Autodesk Inventor part; units mm, degrees
(part 2 of 2)
sketch "Sketch6" plane through (-20, -44, -10) normal (0, -1, 0) x (1, 0, 0)
  arc A0 (32, 4.5) -> (34, 6.5) centre (32, 6.5) ccw projected
  line L0 (34, 13.5) -> (34, 6.5) projected
  arc A1 (34, 13.5) -> (32, 15.5) centre (32, 13.5) ccw projected
  line L1 (8, 15.5) -> (32, 15.5) projected
  arc A2 (8, 15.5) -> (6, 13.5) centre (8, 13.5) ccw projected
  line L2 (6, 6.5) -> (6, 13.5) projected
  arc A3 (6, 6.5) -> (8, 4.5) centre (8, 6.5) ccw projected
  line L3 (32, 4.5) -> (8, 4.5) projected
  line L4 (34, 10) -> (6, 10)
  line L5 (31.2608, 8.1622) -> (8.7392, 8.1622) construction
  line L6 (8.7392, 8.1622) -> (8.7392, 11.8378) construction
  line L7 (8.7392, 11.8378) -> (31.2608, 11.8378) construction
  line L8 (31.2608, 11.8378) -> (31.2608, 8.1622) construction
  line L9 (6, 6.5) -> (6, 13.5) projected
  line L10 (30.8827, 11.2102) -> (30.8856, 8.1622)
  line L11 (30.8856, 8.1622) -> (29.0184, 8.168)
  line L12 (29.0184, 8.168) -> (29.0184, 8.674)
  line L13 (29.0184, 8.674) -> (30.2778, 8.6682)
  line L14 (30.2778, 8.6682) -> (30.2778, 9.375)
  line L15 (30.2778, 9.375) -> (29.2133, 9.375)
  line L16 (29.2133, 9.375) -> (29.2133, 9.8868)
  line L17 (29.2133, 9.8868) -> (30.2778, 9.8868)
  line L18 (30.2778, 9.8868) -> (30.2778, 10.7012)
  line L19 (30.2778, 10.7012) -> (28.9748, 10.7012)
  line L20 (28.9748, 10.7012) -> (28.9748, 11.2102)
  line L21 (28.9748, 11.2102) -> (30.8827, 11.2102)
  line L22 (28.4047, 11.2102) -> (28.4047, 8.9067)
  line L23 (28.4047, 8.9067) -> (27.9132, 8.9067)
  line L24 (27.9132, 8.9067) -> (27.8667, 9.215)
  line L25 (27.8667, 9.215) -> (27.8551, 9.215)
  spline S0 degree 2 poles (27.8551, 9.215) (27.7096, 9.0667) (27.3723, 8.8485) (27.1483, 8.8485) knots 0 0 0 1 2 2 2
  spline S1 degree 2 poles (27.1483, 8.8485) (26.9011, 8.8485) (26.6015, 9.058) (26.5172, 9.2528) knots 0 0 0 1 2 2 2
  spline S2 degree 2 poles (26.5172, 9.2528) (26.3543, 9.0841) (26.0053, 8.8485) (25.7814, 8.8485) knots 0 0 0 1 2 2 2
  spline S3 degree 2 poles (25.7814, 8.8485) (25.412, 8.8485) (25.0717, 9.3401) (25.0717, 9.7763) knots 0 0 0 1 2 2 2
  line L26 (25.0717, 9.7763) -> (25.0717, 11.2102)
  line L27 (25.0717, 11.2102) -> (25.6709, 11.2102)
  line L28 (25.6709, 11.2102) -> (25.6709, 9.849)
  spline S4 degree 2 poles (25.6709, 9.849) (25.6709, 9.5815) (25.8279, 9.3691) (25.9908, 9.3691) knots 0 0 0 1 2 2 2
  spline S5 degree 2 poles (25.9908, 9.3691) (26.0897, 9.3691) (26.3078, 9.4942) (26.4358, 9.628) knots 0 0 0 1 2 2 2
  line L29 (26.4358, 9.628) -> (26.4358, 11.2102)
  line L30 (26.4358, 11.2102) -> (27.0407, 11.2102)
  line L31 (27.0407, 11.2102) -> (27.0407, 9.849)
  spline S6 degree 2 poles (27.0407, 9.849) (27.0407, 9.5815) (27.1978, 9.3691) (27.3606, 9.3691) knots 0 0 0 1 2 2 2
  spline S7 degree 2 poles (27.3606, 9.3691) (27.4566, 9.3691) (27.6806, 9.4942) (27.7998, 9.628) knots 0 0 0 1 2 2 2
  line L32 (27.7998, 9.628) -> (27.7998, 11.2102)
  line L33 (27.7998, 11.2102) -> (28.4047, 11.2102)
  spline S8 degree 2 poles (23.4372, 11.2683) (23.76, 11.2683) (24.2777, 10.9804) (24.586, 10.4365) (24.586, 10.0584) knots 0 0 0 1 2 3 3 3
  spline S9 degree 2 poles (24.586, 10.0584) (24.586, 9.7792) (24.4086, 9.3342) (24.1003, 9.0172) (23.7164, 8.8485) (23.5128, 8.8485) knots 0 0 0 1 2 3 4 4 4
  spline S10 degree 2 poles (23.5128, 8.8485) (23.1958, 8.8485) (22.7683, 9.1336) (22.5501, 9.6309) (22.5501, 9.9508) knots 0 0 0 1 2 3 3 3
  spline S11 degree 2 poles (22.5501, 9.9508) (22.5501, 10.0352) (22.5676, 10.1864) (22.5792, 10.23) knots 0 0 0 1 2 2 2
  line L34 (22.5792, 10.23) -> (23.9985, 10.23)
  spline S12 degree 2 poles (23.9985, 10.23) (23.9723, 10.4162) (23.8008, 10.6721) (23.5274, 10.8001) (23.3558, 10.8001) knots 0 0 0 1 2 3 3 3
  spline S13 degree 2 poles (23.3558, 10.8001) (23.2162, 10.8001) (22.969, 10.7216) (22.841, 10.643) knots 0 0 0 1 2 2 2
  line L35 (22.841, 10.643) -> (22.6374, 11.0124)
  spline S14 degree 2 poles (22.6374, 11.0124) (22.8061, 11.1287) (23.2249, 11.2683) (23.4372, 11.2683) knots 0 0 0 1 2 2 2
  line L36 (24.0102, 9.8229) -> (23.0678, 9.8229)
  spline S15 degree 2 poles (23.0678, 9.8229) (23.0678, 9.5931) (23.2772, 9.3197) (23.5041, 9.3197) knots 0 0 0 1 2 2 2
  spline S16 degree 2 poles (23.5041, 9.3197) (23.6233, 9.3197) (23.8357, 9.4302) (23.984, 9.6571) (24.0102, 9.8229) knots 0 0 0 1 2 3 3 3
  line L37 (22.0499, 11.2102) -> (22.0499, 8.9067)
  line L38 (22.0499, 8.9067) -> (21.5584, 8.9067)
  line L39 (21.5584, 8.9067) -> (21.5118, 9.3139)
  line L40 (21.5118, 9.3139) -> (21.5002, 9.3139)
  spline S17 degree 2 poles (21.5002, 9.3139) (21.3722, 9.087) (21.0261, 8.8485) (20.8458, 8.8485) knots 0 0 0 1 2 2 2
  spline S18 degree 2 poles (20.8458, 8.8485) (20.7469, 8.8485) (20.6277, 8.8776) (20.5782, 8.898) knots 0 0 0 1 2 2 2
  line L41 (20.5782, 8.898) -> (20.6771, 9.4215)
  spline S19 degree 2 poles (20.6771, 9.4215) (20.744, 9.404) (20.8458, 9.3837) (20.9243, 9.3837) knots 0 0 0 1 2 2 2
  spline S20 degree 2 poles (20.9243, 9.3837) (21.0552, 9.3837) (21.3461, 9.5902) (21.445, 9.8374) knots 0 0 0 1 2 2 2
  line L42 (21.445, 9.8374) -> (21.445, 11.2102)
  line L43 (21.445, 11.2102) -> (22.0499, 11.2102)
  spline S21 degree 2 poles (19.444, 12.2107) (19.7145, 12.2107) (20.1507, 12.0827) (20.4008, 11.8238) (20.4008, 11.6173) knots 0 0 0 1 2 3 3 3
  spline S22 degree 2 poles (20.4008, 11.6173) (20.4008, 11.4719) (20.238, 11.2276) (20.0722, 11.1404) knots 0 0 0 1 2 2 2
  line L44 (20.0722, 11.1404) -> (20.0722, 11.12)
  spline S23 degree 2 poles (20.0722, 11.12) (20.1623, 11.0618) (20.2816, 10.8728) (20.2816, 10.7303) knots 0 0 0 1 2 2 2
  spline S24 degree 2 poles (20.2816, 10.7303) (20.2816, 10.6023) (20.1304, 10.3755) (20.0286, 10.2998) knots 0 0 0 1 2 2 2
  line L45 (20.0286, 10.2998) -> (20.0286, 10.2853)
  spline S25 degree 2 poles (20.0286, 10.2853) (20.1478, 10.198) (20.3369, 9.8868) (20.3369, 9.6803) knots 0 0 0 1 2 2 2
  spline S26 degree 2 poles (20.3369, 9.6803) (20.3369, 9.4099) (20.0751, 9.0376) (19.6476, 8.8485) (19.4091, 8.8485) knots 0 0 0 1 2 3 3 3
  spline S27 degree 2 poles (19.4091, 8.8485) (19.3073, 8.8485) (19.1299, 8.8834) (19.0572, 8.9067) knots 0 0 0 1 2 2 2
  line L46 (19.0572, 8.9067) -> (18.2312, 8.9067)
  line L47 (18.2312, 8.9067) -> (18.2312, 9.3517)
  line L48 (18.2312, 9.3517) -> (18.6209, 9.3517)
  spline S28 degree 2 poles (18.6209, 9.3517) (18.5744, 9.4128) (18.5191, 9.5931) (18.5191, 9.7007) knots 0 0 0 1 2 2 2
  spline S29 degree 2 poles (18.5191, 9.7007) (18.5191, 9.9596) (18.7576, 10.3086) (19.1589, 10.4831) (19.4091, 10.4831) knots 0 0 0 1 2 3 3 3
  spline S30 degree 2 poles (19.4091, 10.4831) (19.4731, 10.4831) (19.6272, 10.454) (19.7057, 10.4278) knots 0 0 0 1 2 2 2
  spline S31 degree 2 poles (19.7057, 10.4278) (19.7523, 10.4685) (19.8046, 10.5558) (19.8046, 10.6314) knots 0 0 0 1 2 2 2
  spline S32 degree 2 poles (19.8046, 10.6314) (19.8046, 10.7157) (19.6447, 10.8146) (19.444, 10.8146) knots 0 0 0 1 2 2 2
  line L49 (19.444, 10.8146) -> (19.0484, 10.8146)
  spline S33 degree 2 poles (19.0484, 10.8146) (18.6325, 10.8146) (18.1875, 11.0909) (18.1875, 11.3905) knots 0 0 0 1 2 2 2
  spline S34 degree 2 poles (18.1875, 11.3905) (18.1875, 11.6261) (18.4987, 11.9925) (19.0601, 12.2107) (19.444, 12.2107) knots 0 0 0 1 2 3 3 3
  spline S35 degree 2 poles (19.3538, 11.8238) (19.1764, 11.8238) (18.9176, 11.7337) (18.7692, 11.5853) (18.7692, 11.4952) knots 0 0 0 1 2 3 3 3
  spline S36 degree 2 poles (18.7692, 11.4952) (18.7692, 11.3701) (18.967, 11.2829) (19.1502, 11.2829) knots 0 0 0 1 2 2 2
  line L50 (19.1502, 11.2829) -> (19.4352, 11.2829)
  spline S37 degree 2 poles (19.4352, 11.2829) (19.537, 11.2829) (19.6854, 11.2712) (19.7523, 11.2567) knots 0 0 0 1 2 2 2
  spline S38 degree 2 poles (19.7523, 11.2567) (19.8308, 11.3178) (19.9006, 11.4516) (19.9006, 11.5272) knots 0 0 0 1 2 2 2
  spline S39 degree 2 poles (19.9006, 11.5272) (19.9006, 11.6668) (19.6039, 11.8238) (19.3538, 11.8238) knots 0 0 0 1 2 2 2
  spline S40 degree 2 poles (19.4091, 10.1079) (19.3073, 10.1079) (19.1444, 10.009) (19.0455, 9.817) (19.0455, 9.6803) knots 0 0 0 1 2 3 3 3
  spline S41 degree 2 poles (19.0455, 9.6803) (19.0455, 9.5437) (19.1444, 9.3604) (19.3073, 9.2644) (19.4091, 9.2644) knots 0 0 0 1 2 3 3 3
  spline S42 degree 2 poles (19.4091, 9.2644) (19.508, 9.2644) (19.6737, 9.3604) (19.7668, 9.5437) (19.7668, 9.6803) knots 0 0 0 1 2 3 3 3
  spline S43 degree 2 poles (19.7668, 9.6803) (19.7668, 9.817) (19.6737, 10.009) (19.508, 10.1079) (19.4091, 10.1079) knots 0 0 0 1 2 3 3 3
  spline S44 degree 2 poles (16.7944, 11.2683) (17.1173, 11.2683) (17.6349, 10.9804) (17.9432, 10.4365) (17.9432, 10.0584) knots 0 0 0 1 2 3 3 3
  spline S45 degree 2 poles (17.9432, 10.0584) (17.9432, 9.7792) (17.7658, 9.3342) (17.4575, 9.0172) (17.0736, 8.8485) (16.87, 8.8485) knots 0 0 0 1 2 3 4 4 4
  spline S46 degree 2 poles (16.87, 8.8485) (16.553, 8.8485) (16.1255, 9.1336) (15.9074, 9.6309) (15.9074, 9.9508) knots 0 0 0 1 2 3 3 3
  spline S47 degree 2 poles (15.9074, 9.9508) (15.9074, 10.0352) (15.9248, 10.1864) (15.9364, 10.23) knots 0 0 0 1 2 2 2
  line L51 (15.9364, 10.23) -> (17.3557, 10.23)
  spline S48 degree 2 poles (17.3557, 10.23) (17.3296, 10.4162) (17.158, 10.6721) (16.8846, 10.8001) (16.713, 10.8001) knots 0 0 0 1 2 3 3 3
  spline S49 degree 2 poles (16.713, 10.8001) (16.5734, 10.8001) (16.3262, 10.7216) (16.1982, 10.643) knots 0 0 0 1 2 2 2
  line L52 (16.1982, 10.643) -> (15.9946, 11.0124)
  spline S50 degree 2 poles (15.9946, 11.0124) (16.1633, 11.1287) (16.5821, 11.2683) (16.7944, 11.2683) knots 0 0 0 1 2 2 2
  line L53 (17.3674, 9.8229) -> (16.4251, 9.8229)
  spline S51 degree 2 poles (16.4251, 9.8229) (16.4251, 9.5931) (16.6345, 9.3197) (16.8613, 9.3197) knots 0 0 0 1 2 2 2
  spline S52 degree 2 poles (16.8613, 9.3197) (16.9806, 9.3197) (17.1929, 9.4302) (17.3412, 9.6571) (17.3674, 9.8229) knots 0 0 0 1 2 3 3 3
  line L54 (15.4071, 11.2102) -> (15.4071, 8.9067)
  line L55 (15.4071, 8.9067) -> (14.9156, 8.9067)
  line L56 (14.9156, 8.9067) -> (14.8691, 9.2121)
  line L57 (14.8691, 9.2121) -> (14.8574, 9.2121)
  spline S53 degree 2 poles (14.8574, 9.2121) (14.7033, 9.0638) (14.3426, 8.8485) (14.1071, 8.8485) knots 0 0 0 1 2 2 2
  spline S54 degree 2 poles (14.1071, 8.8485) (13.7348, 8.8485) (13.3974, 9.3401) (13.3974, 9.7763) knots 0 0 0 1 2 2 2
  line L58 (13.3974, 9.7763) -> (13.3974, 11.2102)
  line L59 (13.3974, 11.2102) -> (14.0024, 11.2102)
  line L60 (14.0024, 11.2102) -> (14.0024, 9.849)
  spline S55 degree 2 poles (14.0024, 9.849) (14.0024, 9.5815) (14.1536, 9.3691) (14.3252, 9.3691) knots 0 0 0 1 2 2 2
  spline S56 degree 2 poles (14.3252, 9.3691) (14.4648, 9.3691) (14.6771, 9.5) (14.8022, 9.628) knots 0 0 0 1 2 2 2
  line L61 (14.8022, 9.628) -> (14.8022, 11.2102)
  line L62 (14.8022, 11.2102) -> (15.4071, 11.2102)
  spline S57 degree 2 poles (11.792, 11.2683) (12.109, 11.2683) (12.618, 10.9804) (12.9146, 10.4423) (12.9146, 10.0584) knots 0 0 0 1 2 3 3 3
  spline S58 degree 2 poles (12.9146, 10.0584) (12.9146, 9.6774) (12.5889, 9.1365) (12.0508, 8.8485) (11.7367, 8.8485) knots 0 0 0 1 2 3 3 3
  spline S59 degree 2 poles (11.7367, 8.8485) (11.5244, 8.8485) (11.1958, 8.994) (11.0678, 9.1074) knots 0 0 0 1 2 2 2
  line L63 (11.0678, 9.1074) -> (11.3557, 9.4913)
  spline S60 degree 2 poles (11.3557, 9.4913) (11.4372, 9.4157) (11.6117, 9.343) (11.7047, 9.343) knots 0 0 0 1 2 2 2
  spline S61 degree 2 poles (11.7047, 9.343) (11.8821, 9.343) (12.1497, 9.5204) (12.2922, 9.8403) (12.2922, 10.0584) knots 0 0 0 1 2 3 3 3
  spline S62 degree 2 poles (12.2922, 10.0584) (12.2922, 10.2766) (12.1497, 10.5965) (11.8909, 10.7739) (11.7251, 10.7739) knots 0 0 0 1 2 3 3 3
  spline S63 degree 2 poles (11.7251, 10.7739) (11.6029, 10.7739) (11.3732, 10.6663) (11.2772, 10.5878) knots 0 0 0 1 2 2 2
  line L64 (11.2772, 10.5878) -> (11.0387, 10.9891)
  spline S64 degree 2 poles (11.0387, 10.9891) (11.2045, 11.1316) (11.6029, 11.2683) (11.792, 11.2683) knots 0 0 0 1 2 2 2
  spline S65 degree 2 poles (10.4018, 12.1321) (10.5036, 12.1321) (10.6519, 12.106) (10.7188, 12.0856) knots 0 0 0 1 2 2 2
  line L65 (10.7188, 12.0856) -> (10.6083, 11.6261)
  spline S66 degree 2 poles (10.6083, 11.6261) (10.5734, 11.6348) (10.489, 11.6551) (10.4483, 11.6551) knots 0 0 0 1 2 2 2
  spline S67 degree 2 poles (10.4483, 11.6551) (10.2709, 11.6551) (10.0644, 11.4574) (10.0149, 11.3061) knots 0 0 0 1 2 2 2
  line L66 (10.0149, 11.3061) -> (9.9742, 11.1636)
  line L67 (9.9742, 11.1636) -> (10.87, 8.9067)
  line L68 (10.87, 8.9067) -> (10.2622, 8.9067)
  line L69 (10.2622, 8.9067) -> (9.8957, 9.977)
  spline S68 degree 2 poles (9.8957, 9.977) (9.8434, 10.1341) (9.7532, 10.4627) (9.7038, 10.6256) knots 0 0 0 1 2 2 2
  line L70 (9.7038, 10.6256) -> (9.6834, 10.6256)
  spline S69 degree 2 poles (9.6834, 10.6256) (9.6456, 10.4627) (9.5583, 10.137) (9.5176, 9.977) knots 0 0 0 1 2 2 2
  line L71 (9.5176, 9.977) -> (9.2006, 8.9067)
  line L72 (9.2006, 8.9067) -> (8.6218, 8.9067)
  line L73 (8.6218, 8.9067) -> (9.4391, 11.28)
  spline S70 degree 2 poles (9.4391, 11.28) (9.538, 11.5504) (9.7939, 11.9344) (10.1429, 12.1321) (10.4018, 12.1321) knots 0 0 0 1 2 3 3 3
  point P0 (20, 10)
  point P1 (20, 8.1622)
  point P2 (20, 4.5)
  point P3 (8.7392, 10)
  constraints: 6 midpoint, 2 end point, 1 horizontal alignment, 1 vertical alignment, 2 other
emboss "Emboss1" sketch "Sketch6" operation add depth 0.5 direction (0, 1, 0) contours L10 L11 L12 L13 L14 L15 L16 L17 L18 L4 | L4 L18 L19 L20 L21 L10 | L73 S70 S65 L65 S66 S67 L66 L67 L4 S68 L70 S69 | L4 S69 L71 L72 L73 | L22 L23 L24 L25 S0 S1 S2 S3 L26 L4 L28 S4 S5 L29 L31 S6 S7 L32 | L4 L32 L33 L22 | L4 L67 L68 L69 S68 | L4 L29 L30 L31 | S61 S62 S63 L64 S64 S57 S58 L4 | L4 S58 S59 L63 S60 S61 | L4 L26 L27 L28 | L58 L59 L60 L4 | L4 L60 S55 S56 L61 L54 L55 L56 L57 S53 S54 L58 | S9 S10 S11 L4 | L4 S11 L34 S12 S13 L35 S14 S8 S9 | L61 L62 L54 L4 | L37 L38 L39 L40 S17 S18 L41 S19 S20 L42 L4 | L4 L42 L43 L37 | S47 L51 S48 S49 L52 S50 S44 S45 L4 | L4 S45 S46 S47 | S25 S26 S27 L46 L47 L48 S28 S29 L4 S40 S41 S42 S43 | L4 S43 S40 S29 S30 S31 S32 L49 S33 S34 S21 S22 L44 S23 S24 L45 S25
sketch "Sketch7" plane through (-22.5, 27.5, -10) normal (0, 0, -1) x (-1, 0, 0)
  line L0 (-42.5, -67.5) -> (-2.5, -67.5) projected
  arc A0 (-2.5, -67.5) -> (7.5, -57.5) centre (-2.5, -57.5) ccw projected
  line L1 (7.5, -57.5) -> (7.5, 2.5) projected
  arc A1 (7.5, 2.5) -> (-2.5, 12.5) centre (-2.5, 2.5) ccw projected
  line L2 (-2.5, 12.5) -> (-42.5, 12.5) projected
  arc A2 (-42.5, 12.5) -> (-52.5, 2.5) centre (-42.5, 2.5) ccw projected
  line L3 (-52.5, 2.5) -> (-52.5, -57.5) projected
  arc A3 (-52.5, -57.5) -> (-42.5, -67.5) centre (-42.5, -57.5) ccw projected
  line L4 (-2.5, -64.5) -> (-42.5, -64.5) projected
  arc A4 (-49.5, -57.5) -> (-42.5, -64.5) centre (-42.5, -57.5) ccw projected
  line L5 (-49.5, -57.5) -> (-49.5, 2.5) projected
  arc A5 (-42.5, 9.5) -> (-49.5, 2.5) centre (-42.5, 2.5) ccw projected
  line L6 (-42.5, 9.5) -> (-2.5, 9.5) projected
  arc A6 (4.5, 2.5) -> (-2.5, 9.5) centre (-2.5, 2.5) ccw projected
  line L7 (4.5, 2.5) -> (4.5, -57.5) projected
  arc A7 (-2.5, -64.5) -> (4.5, -57.5) centre (-2.5, -57.5) ccw projected
  line L8 (4.5711, 9.5711) -> (2.4497, 7.4497)
  line L9 (4.5711, -64.5711) -> (2.4497, -62.4497)
  line L10 (-49.5711, -64.5711) -> (-47.4497, -62.4497)
  line L11 (-49.5711, 9.5711) -> (-47.4497, 7.4497)
  circle A8 centre (3.5104, 8.5104) radius 0.75
  circle A9 centre (3.5104, -63.5104) radius 0.75
  circle A10 centre (-48.5104, -63.5104) radius 0.75
  circle A11 centre (-48.5104, 8.5104) radius 0.75
  point P0 (-22.5, -27.5)
  dimension "d30" = 1.5
  constraints: 8 end point, 8 point on circle, 4 centre point, 4 midpoint, 3 equal radius
  measures "d30" diameter of A8
extrude "Extrusion5" cut sketch "Sketch7" against normal blind 10 contours A10 L10 | L10 A10 | A9 L9 | L9 A9 | A11 L11 | L11 A11 | A8 L8 | L8 A8
ref_plane "Work Plane1" through (8, 0, 0) normal (1, 0, 0) x (0, 1, 0)
sketch "Sketch8" plane through (8, 0, 0) normal (1, 0, 0) x (0, 1, 0)
  line L0 (-39.1213, 11.8787) -> (-36, 15) projected
  line L1 (-36, 15) -> (-44, 15)
  line L2 (-45.5, 13.5) -> (-45.5, 13.3787)
  line L3 (-44, 11.8787) -> (-39.1213, 11.8787)
  arc A0 (-45.5, 13.3787) -> (-44, 11.8787) centre (-44, 13.3787) ccw
  arc A1 (-44, 15) -> (-45.5, 13.5) centre (-44, 13.5) ccw
  circle A2 centre (-44.0721, 13.4393) radius 0.6 projected
  circle A3 centre (-44.0721, 13.4393) radius 0.6
  point P0 (0, 0)
  dimension "d34" = 1.5
  dimension "d35" = 8
  dimension "d36" = 1.2
  constraints: 6 end point, 4 point on circle, 4 tangent, 3 centre point, 2 perpendicular, 1 equal radius, 1 horizontal
  measures "d34" radius of A0
  measures "d35" distance of L0.end L1.end
  measures "d36" diameter of A3
extrude "Extrusion6" add sketch "Sketch8" along normal blind 2
mirror "Mirror1" about plane through (0, 0, 0) normal (1, 0, 0) of "Extrusion6"
fillet "Fillet5" radius 0.5 20 edges at (10, -41.5607, 11.8787) (10, -45.5, 13.4393) (10, -45.0607, 14.5607) (10, -40, 15) (10, -45.0607, 12.318) (8, -41.5607, 11.8787) (8, -45.5, 13.4393) (8, -45.0607, 14.5607) (8, -40, 15) (8, -45.0607, 12.318) (-8, -45.0607, 12.318) (-8, -45.5, 13.4393) (-8, -45.0607, 14.5607) (-8, -40, 15) (-8, -41.5607, 11.8787) (-10, -45.0607, 12.318) (-10, -45.5, 13.4393) (-10, -45.0607, 14.5607) (-10, -40, 15) (-10, -41.5607, 11.8787)
mirror "Mirror2" about plane through (0, 0, 0) normal (0, 1, 0) of "Extrusion6", "Mirror1", "Fillet5"
body "Solid1"
